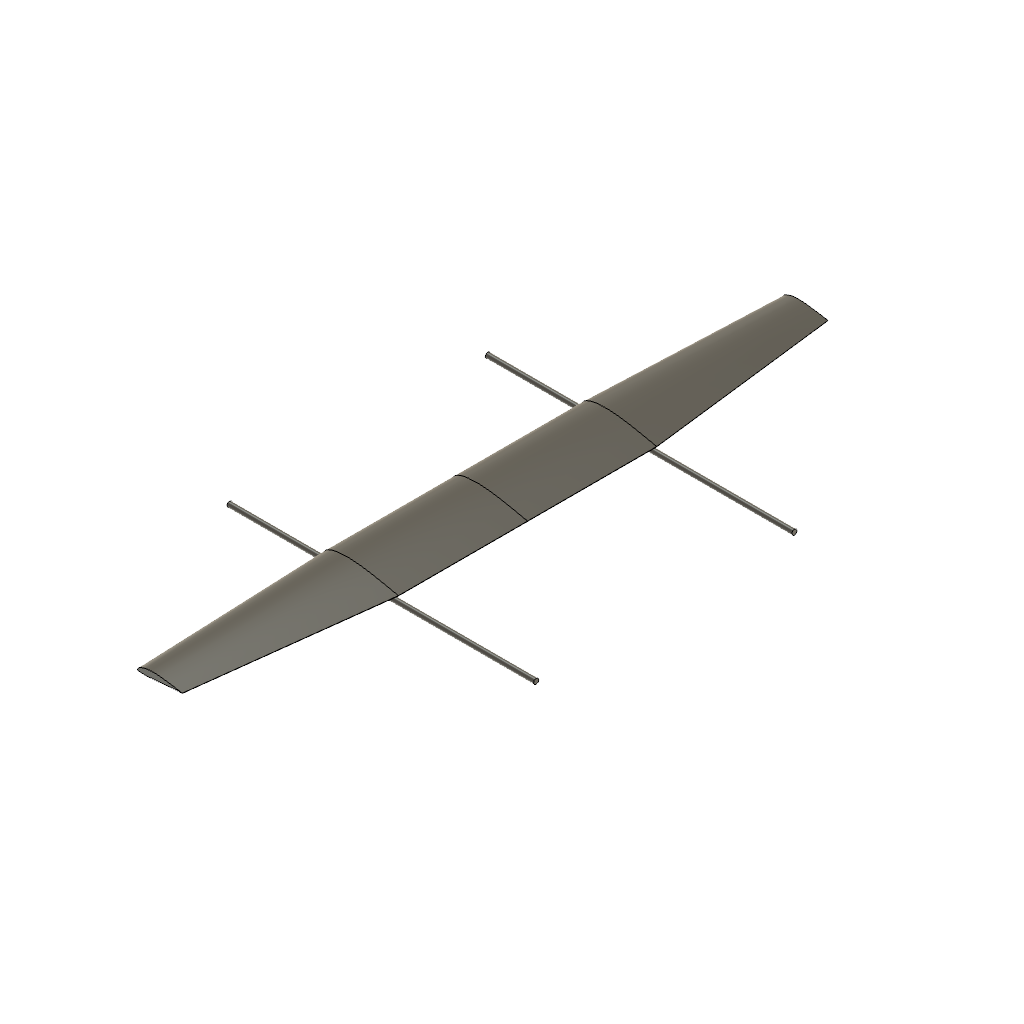
VTOL Wing - Aero OML (Autodesk Fusion 360 design; units mm, degrees)
part number: 2026-10-17-09-22-44-938
part number: 2026-10-17-09-22-45-187
part number: 2026-10-17-09-22-45-715
Autodesk Fusion 360 part; units mm, degrees
(part 1 of 2)
ref_plane "WorkPlane1" through (0, -1000, 0) normal (0, 1, 0) x (0, 0, 1) in component "Wing OML (SD7062, 2 m)"
sketch "Section y=-1000" plane through (0, -1000, 0) normal (0, 1, 0) x (1, 0, 0) in component "Wing OML (SD7062, 2 m)"
  spline S0 degree 5 poles (103.9894, -3.9091) (103.9546, -3.913) (103.8735, -3.9225) (103.7172, -3.942) (103.4393, -3.9785) (102.9897, -4.0405) (102.4668, -4.1159) (101.9003, -4.202) (101.3056, -4.2968) (100.6854, -4.3993) (100.0363, -4.509) (99.3553, -4.6256) (98.6441, -4.7485) (97.906, -4.877) (97.1455, -5.0105) (96.3662, -5.1483) (95.5697, -5.2897) (94.7567, -5.4342) (93.927, -5.5815) (93.0804, -5.7312) (92.2171, -5.883) (91.338, -6.037) (90.444, -6.1931) (89.5363, -6.3512) (88.6159, -6.5114) (87.6835, -6.6736) (86.7397, -6.8378) (85.7847, -7.0039) (84.8189, -7.1719) (83.8425, -7.3417) (82.8558, -7.5131) (81.8592, -7.6861) (80.853, -7.8606) (79.8377, -8.0365) (78.8137, -8.2136) (77.7814, -8.392) (76.7412, -8.5714) (75.6934, -8.7517) (74.6381, -8.9328) (73.5756, -9.1145) (72.506, -9.2967) (71.4297, -9.4792) (70.3468, -9.6618) (69.2576, -9.8446) (68.1623, -10.0272) (67.0611, -10.2097) (65.9544, -10.3918) (64.8422, -10.5733) (63.7249, -10.7541) (62.6025, -10.934) (61.4754, -11.1127) (60.3435, -11.2901) (59.2071, -11.4659) (58.0663, -11.64) (56.9213, -11.8122) (55.7722, -11.9823) (54.6194, -12.1502) (53.4628, -12.3158) (52.3029, -12.479) (51.1396, -12.6396) (49.9733, -12.7975) (48.8041, -12.9525) (47.6321, -13.1045) (46.4575, -13.2533) (45.2804, -13.3986) (44.101, -13.5404) (42.9195, -13.6784) (41.736, -13.8126) (40.5507, -13.9427) (39.3637, -14.0687) (38.1753, -14.1905) (36.9856, -14.3079) (35.7948, -14.4208) (34.603, -14.5291) (33.4104, -14.6328) (32.2172, -14.7315) (31.0236, -14.8251) (29.8296, -14.9136) (28.6355, -14.9967) (27.4415, -15.0742) (26.2477, -15.1461) (25.0543, -15.2122) (23.8616, -15.2723) (22.6696, -15.3263) (21.4787, -15.3742) (20.289, -15.4157) (19.1007, -15.4507) (17.9141, -15.4791) (16.7293, -15.5007) (15.5464, -15.5153) (14.3658, -15.5228) (13.1876, -15.5229) (12.0121, -15.5155) (10.8393, -15.5005) (9.6696, -15.4776) (8.5033, -15.4466) (7.3405, -15.4076) (6.1816, -15.3601) (5.0268, -15.3042) (3.8764, -15.2395) (2.7307, -15.1659) (1.59, -15.0831) (0.4545, -14.9909) (-0.6753, -14.8891) (-1.7992, -14.7774) (-2.9169, -14.6555) (-4.0279, -14.5234) (-5.1321, -14.3808) (-6.229, -14.2276) (-7.3182, -14.0636) (-8.3993, -13.8885) (-9.4719, -13.7021) (-10.5354, -13.5041) (-11.5894, -13.2942) (-12.6332, -13.072) (-13.6663, -12.8371) (-14.688, -12.5894) (-15.698, -12.3284) (-16.6955, -12.0542) (-17.6801, -11.7667) (-18.6511, -11.4659) (-19.6079, -11.1515) (-20.5497, -10.8236) (-21.4754, -10.4816) (-22.3839, -10.125) (-23.2739, -9.753) (-24.1438, -9.3652) (-24.9925, -8.9612) (-25.8188, -8.5411) (-26.622, -8.1055) (-27.4012, -7.6554) (-28.1556, -7.1919) (-28.8836, -6.7153) (-29.5829, -6.2254) (-30.2501, -5.7205) (-30.8811, -5.1987) (-31.4722, -4.6589) (-32.0202, -4.1021) (-32.5241, -3.5326) (-32.9845, -2.9586) (-33.4012, -2.3876) (-33.7716, -1.824) (-34.0876, -1.2648) (-34.3357, -0.6996) (-34.5057, -0.1267) (-34.5969, 0.4365) (-34.6273, 0.9351) (-34.6253, 1.3136) (-34.616, 1.5684) (-34.6144, 1.7803) (-34.5603, 2.036) (-34.36, 2.3782) (-34.0098, 2.7656) (-33.5512, 3.1223) (-33.028, 3.3992) (-32.4588, 3.6037) (-31.8511, 3.7667) (-31.2056, 3.9223) (-30.5251, 4.0821) (-29.8136, 4.2426) (-29.0752, 4.3929) (-28.3137, 4.5228) (-27.5314, 4.6297) (-26.7298, 4.7165) (-25.9098, 4.7888) (-25.072, 4.853) (-24.217, 4.9126) (-23.3459, 4.9686) (-22.4595, 5.0198) (-21.5588, 5.0647) (-20.6447, 5.1014) (-19.7181, 5.1293) (-18.7794, 5.1485) (-17.8292, 5.16) (-16.868, 5.1651) (-15.8961, 5.1647) (-14.9139, 5.1598) (-13.9218, 5.1506) (-12.9203, 5.1371) (-11.9098, 5.1191) (-10.8907, 5.0965) (-9.8633, 5.0689) (-8.828, 5.0366) (-7.7851, 4.9996) (-6.7349, 4.9582) (-5.6776, 4.9128) (-4.6137, 4.8637) (-3.5432, 4.8112) (-2.4665, 4.7554) (-1.3838, 4.6965) (-0.2955, 4.6343) (0.7984, 4.5691) (1.8974, 4.5008) (3.0014, 4.4294) (4.1101, 4.355) (5.2234, 4.2777) (6.341, 4.1977) (7.4628, 4.1151) (8.5884, 4.0299) (9.7178, 3.9423) (10.8507, 3.8523) (11.987, 3.76) (13.1265, 3.6655) (14.269, 3.5688) (15.4143, 3.47) (16.5622, 3.3691) (17.7126, 3.2661) (18.8653, 3.1613) (20.02, 3.0547) (21.1766, 2.9464) (22.335, 2.8365) (23.4948, 2.7252) (24.6561, 2.6126) (25.8186, 2.4988) (26.9821, 2.3839) (28.1467, 2.268) (29.312, 2.1512) (30.478, 2.0337) (31.6445, 1.9154) (32.8114, 1.7964) (33.9784, 1.677) (35.1455, 1.5571) (36.3124, 1.4369) (37.479, 1.3164) (38.6451, 1.1957) (39.8105, 1.0749) (40.9751, 0.9542) (42.1387, 0.8336) (43.3011, 0.7133) (44.4623, 0.5932) (45.6221, 0.4736) (46.7803, 0.3545) (47.9367, 0.236) (49.0912, 0.1182) (50.2436, 0.0011) (51.3938, -0.1151) (52.5415, -0.2305) (53.6867, -0.3449) (54.8291, -0.4582) (55.9685, -0.5704) (57.1048, -0.6815) (58.2378, -0.7912) (59.3672, -0.8996) (60.4929, -1.0066) (61.6147, -1.1122) (62.7324, -1.2161) (63.8458, -1.3185) (64.9547, -1.4192) (66.0589, -1.5182) (67.1581, -1.6153) (68.2522, -1.7106) (69.3409, -1.8039) (70.4239, -1.8952) (71.5011, -1.9843) (72.5722, -2.0713) (73.6369, -2.156) (74.6949, -2.2385) (75.7461, -2.3187) (76.7902, -2.3965) (77.8269, -2.472) (78.8559, -2.5452) (79.8769, -2.616) (80.8895, -2.6844) (81.8933, -2.7502) (82.8878, -2.8135) (83.8727, -2.874) (84.8475, -2.9317) (85.8119, -2.9865) (86.7656, -3.0383) (87.7083, -3.0873) (88.6398, -3.1332) (89.5596, -3.1762) (90.4669, -3.2162) (91.3608, -3.2531) (92.2403, -3.2868) (93.1042, -3.3172) (93.9516, -3.3443) (94.782, -3.3679) (95.5956, -3.3879) (96.3925, -3.4044) (97.1722, -3.4173) (97.9332, -3.4267) (98.6724, -3.4331) (99.3851, -3.4365) (100.0673, -3.4373) (100.7169, -3.4355) (101.3362, -3.4305) (101.9288, -3.4217) (102.4929, -3.4091) (103.0142, -3.3935) (103.4629, -3.3776) (103.7397, -3.3666) (103.8946, -3.3599) (103.9746, -3.3561) (104.0088, -3.3544) knots 0 0 0 0 0 0 0.00344828 0.00689655 0.01034483 0.0137931 0.01724138 0.02068966 0.02413793 0.02758621 0.03103448 0.03448276 0.03793103 0.04137931 0.04482759 0.04827586 0.05172414 0.05517241 0.05862069 0.06206897 0.06551724 0.06896552 0.07241379 0.07586207 0.07931034 0.08275862 0.0862069 0.08965517 0.09310345 0.09655172 0.1 0.10344828 0.10689655 0.11034483 0.1137931 0.11724138 0.12068966 0.12413793 0.12758621 0.13103448 0.13448276 0.13793103 0.14137931 0.14482759 0.14827586 0.15172414 0.15517241 0.15862069 0.16206897 0.16551724 0.16896552 0.17241379 0.17586207 0.17931034 0.18275862 0.1862069 0.18965517 0.19310345 0.19655172 0.2 0.20344828 0.20689655 0.21034483 0.2137931 0.21724138 0.22068966 0.22413793 0.22758621 0.23103448 0.23448276 0.23793103 0.24137931 0.24482759 0.24827586 0.25172414 0.25517241 0.25862069 0.26206897 0.26551724 0.26896552 0.27241379 0.27586207 0.27931034 0.28275862 0.2862069 0.28965517 0.29310345 0.29655172 0.3 0.30344828 0.30689655 0.31034483 0.3137931 0.31724138 0.32068966 0.32413793 0.32758621 0.33103448 0.33448276 0.33793103 0.34137931 0.34482759 0.34827586 0.35172414 0.35517241 0.35862069 0.36206897 0.36551724 0.36896552 0.37241379 0.37586207 0.37931034 0.38275862 0.3862069 0.38965517 0.39310345 0.39655172 0.4 0.40344828 0.40689655 0.41034483 0.4137931 0.41724138 0.42068966 0.42413793 0.42758621 0.43103448 0.43448276 0.43793103 0.44137931 0.44482759 0.44827586 0.45172414 0.45517241 0.45862069 0.46206897 0.46551724 0.46896552 0.47241379 0.47586207 0.47931034 0.48275862 0.4862069 0.48965517 0.49310345 0.49655172 0.5 0.50344828 0.50689655 0.51034483 0.5137931 0.51724138 0.52068966 0.52413793 0.52758621 0.53103448 0.53448276 0.53793103 0.54137931 0.54482759 0.54827586 0.55172414 0.55517241 0.55862069 0.56206897 0.56551724 0.56896552 0.57241379 0.57586207 0.57931034 0.58275862 0.5862069 0.58965517 0.59310345 0.59655172 0.6 0.60344828 0.60689655 0.61034483 0.6137931 0.61724138 0.62068966 0.62413793 0.62758621 0.63103448 0.63448276 0.63793103 0.64137931 0.64482759 0.64827586 0.65172414 0.65517241 0.65862069 0.66206897 0.66551724 0.66896552 0.67241379 0.67586207 0.67931034 0.68275862 0.6862069 0.68965517 0.69310345 0.69655172 0.7 0.70344828 0.70689655 0.71034483 0.7137931 0.71724138 0.72068966 0.72413793 0.72758621 0.73103448 0.73448276 0.73793103 0.74137931 0.74482759 0.74827586 0.75172414 0.75517241 0.75862069 0.76206897 0.76551724 0.76896552 0.77241379 0.77586207 0.77931034 0.78275862 0.7862069 0.78965517 0.79310345 0.79655172 0.8 0.80344828 0.80689655 0.81034483 0.8137931 0.81724138 0.82068966 0.82413793 0.82758621 0.83103448 0.83448276 0.83793103 0.84137931 0.84482759 0.84827586 0.85172414 0.85517241 0.85862069 0.86206897 0.86551724 0.86896552 0.87241379 0.87586207 0.87931034 0.88275862 0.8862069 0.88965517 0.89310345 0.89655172 0.9 0.90344828 0.90689655 0.91034483 0.9137931 0.91724138 0.92068966 0.92413793 0.92758621 0.93103448 0.93448276 0.93793103 0.94137931 0.94482759 0.94827586 0.95172414 0.95517241 0.95862069 0.96206897 0.96551724 0.96896552 0.97241379 0.97586207 0.97931034 0.98275862 0.9862069 0.98965517 0.99310345 0.99655172 1 1 1 1 1 1
  line L0 (104.0088, -3.3544) -> (103.9894, -3.9091)
  point P0 (103.5655, -3.9623)
  point P1 (102.3014, -4.1417)
  point P2 (100.2182, -4.4785)
  point P3 (97.3408, -4.9764)
  point P4 (93.7017, -5.6212)
  point P5 (89.3406, -6.3852)
  point P6 (84.3092, -7.2605)
  point P7 (78.6647, -8.2393)
  point P8 (72.4745, -9.3018)
  point P9 (65.8062, -10.4157)
  point P10 (58.7351, -11.5376)
  point P11 (51.3352, -12.612)
  point P12 (43.6916, -13.5877)
  point P13 (35.8909, -14.4107)
  point P14 (28.0249, -15.0357)
  point P15 (20.1882, -15.4173)
  point P16 (12.4822, -15.5175)
  point P17 (5.0052, -15.3008)
  point P18 (-2.1363, -14.739)
  point P19 (-8.836, -13.8109)
  point P20 (-14.984, -12.5105)
  point P21 (-20.4695, -10.8473)
  point P22 (-25.1803, -8.8613)
  point P23 (-29.0048, -6.6244)
  point P24 (-31.8531, -4.2633)
  point P25 (-33.6642, -1.976)
  point P26 (-34.5072, -0.0348)
  point P27 (-34.6239, 1.2341)
  point P28 (-34.6131, 1.6627)
  point P29 (-34.5228, 2.0608)
  point P30 (-33.6919, 2.9953)
  point P31 (-31.8211, 3.7699)
  point P32 (-29.084, 4.3852)
  point P33 (-25.5593, 4.8146)
  point P34 (-21.3144, 5.0732)
  point P35 (-16.409, 5.1643)
  point P36 (-10.908, 5.0957)
  point P37 (-4.8792, 4.8755)
  point P38 (1.6044, 4.5186)
  point P39 (8.4642, 4.0388)
  point P40 (15.62, 3.4516)
  point P41 (22.9893, 2.7736)
  point P42 (30.4841, 2.0329)
  point P43 (38.0222, 1.2601)
  point P44 (45.5144, 0.4848)
  point P45 (52.8757, -0.2637)
  point P46 (60.0221, -0.9617)
  point P47 (66.8697, -1.5896)
  point P48 (73.3385, -2.132)
  point P49 (79.3538, -2.5795)
  point P50 (84.8436, -2.9309)
  point P51 (89.7426, -3.1839)
  point P52 (93.9922, -3.3448)
  point P53 (97.5409, -3.4215)
  point P54 (100.3463, -3.4361)
  point P55 (102.3727, -3.4111)
  point P56 (103.5986, -3.372)
ref_plane "WorkPlane2" through (0, -400, 0) normal (0, 1, 0) x (0, 0, 1) in component "Wing OML (SD7062, 2 m)"
sketch "Section y=-400" plane through (0, -400, 0) normal (0, 1, 0) x (1, 0, 0) in component "Wing OML (SD7062, 2 m)"
  spline S0 degree 5 poles (173.4375, -0.4625) (173.3779, -0.4713) (173.2398, -0.4925) (172.9754, -0.5349) (172.508, -0.6131) (171.7554, -0.7438) (170.8834, -0.9011) (169.9408, -1.0785) (168.9525, -1.2718) (167.9224, -1.4794) (166.8445, -1.7007) (165.7141, -1.9352) (164.5339, -2.1819) (163.3097, -2.4395) (162.0489, -2.7065) (160.7573, -2.9816) (159.4376, -3.2638) (158.0906, -3.5521) (156.7161, -3.8459) (155.3137, -4.1446) (153.8838, -4.4479) (152.4278, -4.7557) (150.9472, -5.0677) (149.4441, -5.3839) (147.9201, -5.7042) (146.3763, -6.0287) (144.8138, -6.3571) (143.2329, -6.6894) (141.6342, -7.0253) (140.018, -7.3648) (138.3848, -7.7076) (136.7352, -8.0536) (135.0699, -8.4027) (133.3896, -8.7546) (131.695, -9.1091) (129.9867, -9.4661) (128.2654, -9.8252) (126.5313, -10.1863) (124.7851, -10.5491) (123.0268, -10.9133) (121.257, -11.2787) (119.476, -11.645) (117.684, -12.012) (115.8816, -12.3794) (114.069, -12.747) (112.2468, -13.1147) (110.4153, -13.482) (108.5748, -13.8487) (106.7256, -14.2145) (104.8681, -14.5791) (103.0025, -14.942) (101.1291, -15.3029) (99.248, -15.6615) (97.3595, -16.0174) (95.464, -16.3704) (93.5617, -16.7202) (91.6529, -17.0666) (89.7379, -17.4093) (87.817, -17.7482) (85.8906, -18.083) (83.9589, -18.4134) (82.0221, -18.7393) (80.0807, -19.0603) (78.1347, -19.376) (76.1844, -19.6862) (74.2301, -19.9906) (72.2721, -20.2889) (70.3105, -20.5809) (68.3457, -20.8663) (66.3779, -21.1449) (64.4074, -21.4165) (62.4345, -21.681) (60.4595, -21.9381) (58.4827, -22.1876) (56.5043, -22.4294) (54.5246, -22.663) (52.5438, -22.8882) (50.5622, -23.1048) (48.5801, -23.3125) (46.5977, -23.511) (44.6154, -23.7) (42.6334, -23.8794) (40.6522, -24.0488) (38.6719, -24.2081) (36.693, -24.357) (34.7157, -24.4954) (32.7404, -24.6228) (30.7674, -24.7392) (28.797, -24.8442) (26.8296, -24.9374) (24.8654, -25.0186) (22.9047, -25.0875) (20.948, -25.1438) (18.9955, -25.1871) (17.0477, -25.2173) (15.1049, -25.2339) (13.1675, -25.2367) (11.2361, -25.2255) (9.3109, -25.1999) (7.3926, -25.1595) (5.4815, -25.104) (3.5781, -25.0329) (1.683, -24.9459) (-0.2034, -24.8426) (-2.0806, -24.7225) (-3.948, -24.5852) (-5.8051, -24.4305) (-7.6513, -24.2579) (-9.4861, -24.0673) (-11.3088, -23.8582) (-13.1187, -23.6303) (-14.9152, -23.3831) (-16.6973, -23.1162) (-18.4643, -22.8288) (-20.2152, -22.5205) (-21.949, -22.1905) (-23.6649, -21.8383) (-25.3618, -21.4636) (-27.039, -21.0661) (-28.6954, -20.6457) (-30.3303, -20.2023) (-31.9423, -19.7357) (-33.5302, -19.2456) (-35.0925, -18.7312) (-36.627, -18.1914) (-38.1316, -17.6252) (-39.604, -17.0314) (-41.0421, -16.4093) (-42.4441, -15.7591) (-43.8086, -15.0816) (-45.1342, -14.3787) (-46.4193, -13.6517) (-47.6616, -12.9015) (-48.8572, -12.1275) (-50.0006, -11.3267) (-51.0851, -10.4957) (-52.1043, -9.6324) (-53.0531, -8.7378) (-53.9292, -7.819) (-54.7331, -6.8893) (-55.4645, -5.9614) (-56.1187, -5.043) (-56.6829, -4.1292) (-57.135, -3.2016) (-57.4573, -2.2557) (-57.647, -1.3186) (-57.7297, -0.4816) (-57.7502, 0.1595) (-57.7499, 0.5935) (-57.7591, 0.9541) (-57.6812, 1.3907) (-57.3606, 1.9785) (-56.7919, 2.6466) (-56.042, 3.2659) (-55.1817, 3.7543) (-54.2419, 4.1256) (-53.2361, 4.4315) (-52.167, 4.7287) (-51.04, 5.0349) (-49.8616, 5.3437) (-48.6381, 5.6364) (-47.3752, 5.8957) (-46.0767, 6.118) (-44.7453, 6.3081) (-43.3825, 6.4756) (-41.9898, 6.6308) (-40.5684, 6.7797) (-39.1198, 6.9232) (-37.6457, 7.0599) (-36.1476, 7.1866) (-34.6269, 7.3004) (-33.0848, 7.4001) (-31.5223, 7.4862) (-29.9403, 7.5603) (-28.3396, 7.6242) (-26.721, 7.6798) (-25.085, 7.7285) (-23.4324, 7.7706) (-21.764, 7.8062) (-20.0803, 7.8348) (-18.3821, 7.8561) (-16.6699, 7.8697) (-14.9443, 7.8758) (-13.2058, 7.8746) (-11.455, 7.8666) (-9.6924, 7.8523) (-7.9183, 7.8323) (-6.1333, 7.807) (-4.3378, 7.7766) (-2.5322, 7.7412) (-0.7169, 7.701) (1.1075, 7.6558) (2.9408, 7.6059) (4.7825, 7.5511) (6.6322, 7.4917) (8.4896, 7.4277) (10.3544, 7.3594) (12.2261, 7.2869) (14.1044, 7.2105) (15.9891, 7.1303) (17.8799, 7.0463) (19.7763, 6.9588) (21.6781, 6.8677) (23.5851, 6.7731) (25.4968, 6.6752) (27.4131, 6.5739) (29.3335, 6.4694) (31.2577, 6.3619) (33.1855, 6.2515) (35.1166, 6.1385) (37.0505, 6.023) (38.9871, 5.9052) (40.9261, 5.7853) (42.8672, 5.6634) (44.8102, 5.5398) (46.7548, 5.4146) (48.7007, 5.288) (50.6479, 5.1601) (52.5959, 5.031) (54.5445, 4.901) (56.4935, 4.77) (58.4425, 4.6383) (60.3913, 4.506) (62.3396, 4.3733) (64.2871, 4.2403) (66.2334, 4.1071) (68.1784, 3.9738) (70.1218, 3.8408) (72.0632, 3.708) (74.0025, 3.5758) (75.9394, 3.4441) (77.8737, 3.3132) (79.805, 3.1832) (81.7331, 3.0542) (83.6577, 2.9264) (85.5785, 2.7997) (87.4953, 2.6744) (89.4077, 2.5506) (91.3155, 2.4284) (93.2183, 2.3078) (95.1159, 2.189) (97.0078, 2.0721) (98.8938, 1.9573) (100.7736, 1.8446) (102.6468, 1.7341) (104.5131, 1.626) (106.3722, 1.5203) (108.2237, 1.4171) (110.0673, 1.3165) (111.9026, 1.2186) (113.7293, 1.1235) (115.5469, 1.0314) (117.3551, 0.9423) (119.1534, 0.8564) (120.9414, 0.7738) (122.7188, 0.6946) (124.485, 0.6187) (126.2397, 0.5463) (127.9825, 0.4773) (129.713, 0.4117) (131.4306, 0.3496) (133.1347, 0.2909) (134.8248, 0.2358) (136.5002, 0.1844) (138.1601, 0.1368) (139.8038, 0.0932) (141.4307, 0.0536) (143.0402, 0.0183) (144.6317, -0.0128) (146.205, -0.0397) (147.7594, -0.0622) (149.2942, -0.0805) (150.8084, -0.0944) (152.3002, -0.1041) (153.7678, -0.1093) (155.2095, -0.1099) (156.6237, -0.1059) (158.0095, -0.0971) (159.3671, -0.0834) (160.6968, -0.0647) (161.9979, -0.041) (163.2682, -0.0127) (164.5022, 0.0197) (165.6923, 0.0553) (166.8319, 0.0935) (167.9171, 0.1343) (168.9516, 0.1785) (169.9416, 0.2275) (170.8846, 0.2813) (171.7577, 0.3377) (172.5117, 0.3908) (172.9791, 0.4257) (173.2421, 0.4462) (173.3788, 0.4575) (173.4375, 0.4625) knots 0 0 0 0 0 0 0.00344828 0.00689655 0.01034483 0.0137931 0.01724138 0.02068966 0.02413793 0.02758621 0.03103448 0.03448276 0.03793103 0.04137931 0.04482759 0.04827586 0.05172414 0.05517241 0.05862069 0.06206897 0.06551724 0.06896552 0.07241379 0.07586207 0.07931034 0.08275862 0.0862069 0.08965517 0.09310345 0.09655172 0.1 0.10344828 0.10689655 0.11034483 0.1137931 0.11724138 0.12068966 0.12413793 0.12758621 0.13103448 0.13448276 0.13793103 0.14137931 0.14482759 0.14827586 0.15172414 0.15517241 0.15862069 0.16206897 0.16551724 0.16896552 0.17241379 0.17586207 0.17931034 0.18275862 0.1862069 0.18965517 0.19310345 0.19655172 0.2 0.20344828 0.20689655 0.21034483 0.2137931 0.21724138 0.22068966 0.22413793 0.22758621 0.23103448 0.23448276 0.23793103 0.24137931 0.24482759 0.24827586 0.25172414 0.25517241 0.25862069 0.26206897 0.26551724 0.26896552 0.27241379 0.27586207 0.27931034 0.28275862 0.2862069 0.28965517 0.29310345 0.29655172 0.3 0.30344828 0.30689655 0.31034483 0.3137931 0.31724138 0.32068966 0.32413793 0.32758621 0.33103448 0.33448276 0.33793103 0.34137931 0.34482759 0.34827586 0.35172414 0.35517241 0.35862069 0.36206897 0.36551724 0.36896552 0.37241379 0.37586207 0.37931034 0.38275862 0.3862069 0.38965517 0.39310345 0.39655172 0.4 0.40344828 0.40689655 0.41034483 0.4137931 0.41724138 0.42068966 0.42413793 0.42758621 0.43103448 0.43448276 0.43793103 0.44137931 0.44482759 0.44827586 0.45172414 0.45517241 0.45862069 0.46206897 0.46551724 0.46896552 0.47241379 0.47586207 0.47931034 0.48275862 0.4862069 0.48965517 0.49310345 0.49655172 0.5 0.50344828 0.50689655 0.51034483 0.5137931 0.51724138 0.52068966 0.52413793 0.52758621 0.53103448 0.53448276 0.53793103 0.54137931 0.54482759 0.54827586 0.55172414 0.55517241 0.55862069 0.56206897 0.56551724 0.56896552 0.57241379 0.57586207 0.57931034 0.58275862 0.5862069 0.58965517 0.59310345 0.59655172 0.6 0.60344828 0.60689655 0.61034483 0.6137931 0.61724138 0.62068966 0.62413793 0.62758621 0.63103448 0.63448276 0.63793103 0.64137931 0.64482759 0.64827586 0.65172414 0.65517241 0.65862069 0.66206897 0.66551724 0.66896552 0.67241379 0.67586207 0.67931034 0.68275862 0.6862069 0.68965517 0.69310345 0.69655172 0.7 0.70344828 0.70689655 0.71034483 0.7137931 0.71724138 0.72068966 0.72413793 0.72758621 0.73103448 0.73448276 0.73793103 0.74137931 0.74482759 0.74827586 0.75172414 0.75517241 0.75862069 0.76206897 0.76551724 0.76896552 0.77241379 0.77586207 0.77931034 0.78275862 0.7862069 0.78965517 0.79310345 0.79655172 0.8 0.80344828 0.80689655 0.81034483 0.8137931 0.81724138 0.82068966 0.82413793 0.82758621 0.83103448 0.83448276 0.83793103 0.84137931 0.84482759 0.84827586 0.85172414 0.85517241 0.85862069 0.86206897 0.86551724 0.86896552 0.87241379 0.87586207 0.87931034 0.88275862 0.8862069 0.88965517 0.89310345 0.89655172 0.9 0.90344828 0.90689655 0.91034483 0.9137931 0.91724138 0.92068966 0.92413793 0.92758621 0.93103448 0.93448276 0.93793103 0.94137931 0.94482759 0.94827586 0.95172414 0.95517241 0.95862069 0.96206897 0.96551724 0.96896552 0.97241379 0.97586207 0.97931034 0.98275862 0.9862069 0.98965517 0.99310345 0.99655172 1 1 1 1 1 1
  line L0 (173.4375, 0.4625) -> (173.4375, -0.4625)
  point P0 (172.7345, -0.5758)
  point P1 (170.6394, -0.9481)
  point P2 (167.1891, -1.6303)
  point P3 (162.4254, -2.627)
  point P4 (156.4013, -3.9128)
  point P5 (149.1817, -5.439)
  point P6 (140.8521, -7.1896)
  point P7 (131.5072, -9.1482)
  point P8 (121.2583, -11.2781)
  point P9 (110.2161, -13.5212)
  point P10 (98.5032, -15.8013)
  point P11 (86.2401, -18.0213)
  point P12 (73.5652, -20.091)
  point P13 (60.6199, -21.9156)
  point P14 (47.5542, -23.4141)
  point P15 (34.5233, -24.5056)
  point P16 (21.6936, -25.1207)
  point P17 (9.2269, -25.1947)
  point P18 (-2.701, -24.6744)
  point P19 (-13.9143, -23.5181)
  point P20 (-24.2304, -21.7097)
  point P21 (-33.4642, -19.2585)
  point P22 (-41.4261, -16.2245)
  point P23 (-47.9266, -12.7211)
  point P24 (-52.8083, -8.954)
  point P25 (-55.9579, -5.2494)
  point P26 (-57.4749, -2.0651)
  point P27 (-57.7431, 0.0416)
  point P28 (-57.7501, 0.7562)
  point P29 (-57.6229, 1.4245)
  point P30 (-56.2932, 3.0294)
  point P31 (-53.2222, 4.4284)
  point P32 (-48.6989, 5.6124)
  point P33 (-42.8529, 6.5328)
  point P34 (-35.7975, 7.2104)
  point P35 (-27.6321, 7.6474)
  point P36 (-18.4653, 7.8532)
  point P37 (-8.4106, 7.8371)
  point P38 (2.4096, 7.6197)
  point P39 (13.8634, 7.2196)
  point P40 (25.8168, 6.6577)
  point P41 (38.1308, 5.957)
  point P42 (50.6576, 5.1592)
  point P43 (63.2584, 4.3105)
  point P44 (75.7829, 3.4549)
  point P45 (88.0877, 2.6362)
  point P46 (100.0318, 1.8893)
  point P47 (111.4741, 1.2418)
  point P48 (122.2804, 0.7146)
  point P49 (132.3259, 0.3191)
  point P50 (141.4903, 0.0532)
  point P51 (149.665, -0.0833)
  point P52 (156.7528, -0.1041)
  point P53 (162.6682, -0.0254)
  point P54 (167.3417, 0.1133)
  point P55 (170.7157, 0.2729)
  point P56 (172.7553, 0.4093)
sketch "Section y=0" plane through (0, 0, 0) normal (0, 1, 0) x (1, 0, 0) in component "Wing OML (SD7062, 2 m)"
  spline S0 degree 5 poles (173.4375, -0.4625) (173.3779, -0.4713) (173.2398, -0.4925) (172.9754, -0.5349) (172.508, -0.6131) (171.7554, -0.7438) (170.8834, -0.9011) (169.9408, -1.0785) (168.9525, -1.2718) (167.9224, -1.4794) (166.8445, -1.7007) (165.7141, -1.9352) (164.5339, -2.1819) (163.3097, -2.4395) (162.0489, -2.7065) (160.7573, -2.9816) (159.4376, -3.2638) (158.0906, -3.5521) (156.7161, -3.8459) (155.3137, -4.1446) (153.8838, -4.4479) (152.4278, -4.7557) (150.9472, -5.0677) (149.4441, -5.3839) (147.9201, -5.7042) (146.3763, -6.0287) (144.8138, -6.3571) (143.2329, -6.6894) (141.6342, -7.0253) (140.018, -7.3648) (138.3848, -7.7076) (136.7352, -8.0536) (135.0699, -8.4027) (133.3896, -8.7546) (131.695, -9.1091) (129.9867, -9.4661) (128.2654, -9.8252) (126.5313, -10.1863) (124.7851, -10.5491) (123.0268, -10.9133) (121.257, -11.2787) (119.476, -11.645) (117.684, -12.012) (115.8816, -12.3794) (114.069, -12.747) (112.2468, -13.1147) (110.4153, -13.482) (108.5748, -13.8487) (106.7256, -14.2145) (104.8681, -14.5791) (103.0025, -14.942) (101.1291, -15.3029) (99.248, -15.6615) (97.3595, -16.0174) (95.464, -16.3704) (93.5617, -16.7202) (91.6529, -17.0666) (89.7379, -17.4093) (87.817, -17.7482) (85.8906, -18.083) (83.9589, -18.4134) (82.0221, -18.7393) (80.0807, -19.0603) (78.1347, -19.376) (76.1844, -19.6862) (74.2301, -19.9906) (72.2721, -20.2889) (70.3105, -20.5809) (68.3457, -20.8663) (66.3779, -21.1449) (64.4074, -21.4165) (62.4345, -21.681) (60.4595, -21.9381) (58.4827, -22.1876) (56.5043, -22.4294) (54.5246, -22.663) (52.5438, -22.8882) (50.5622, -23.1048) (48.5801, -23.3125) (46.5977, -23.511) (44.6154, -23.7) (42.6334, -23.8794) (40.6522, -24.0488) (38.6719, -24.2081) (36.693, -24.357) (34.7157, -24.4954) (32.7404, -24.6228) (30.7674, -24.7392) (28.797, -24.8442) (26.8296, -24.9374) (24.8654, -25.0186) (22.9047, -25.0875) (20.948, -25.1438) (18.9955, -25.1871) (17.0477, -25.2173) (15.1049, -25.2339) (13.1675, -25.2367) (11.2361, -25.2255) (9.3109, -25.1999) (7.3926, -25.1595) (5.4815, -25.104) (3.5781, -25.0329) (1.683, -24.9459) (-0.2034, -24.8426) (-2.0806, -24.7225) (-3.948, -24.5852) (-5.8051, -24.4305) (-7.6513, -24.2579) (-9.4861, -24.0673) (-11.3088, -23.8582) (-13.1187, -23.6303) (-14.9152, -23.3831) (-16.6973, -23.1162) (-18.4643, -22.8288) (-20.2152, -22.5205) (-21.949, -22.1905) (-23.6649, -21.8383) (-25.3618, -21.4636) (-27.039, -21.0661) (-28.6954, -20.6457) (-30.3303, -20.2023) (-31.9423, -19.7357) (-33.5302, -19.2456) (-35.0925, -18.7312) (-36.627, -18.1914) (-38.1316, -17.6252) (-39.604, -17.0314) (-41.0421, -16.4093) (-42.4441, -15.7591) (-43.8086, -15.0816) (-45.1342, -14.3787) (-46.4193, -13.6517) (-47.6616, -12.9015) (-48.8572, -12.1275) (-50.0006, -11.3267) (-51.0851, -10.4957) (-52.1043, -9.6324) (-53.0531, -8.7378) (-53.9292, -7.819) (-54.7331, -6.8893) (-55.4645, -5.9614) (-56.1187, -5.043) (-56.6829, -4.1292) (-57.135, -3.2016) (-57.4573, -2.2557) (-57.647, -1.3186) (-57.7297, -0.4816) (-57.7502, 0.1595) (-57.7499, 0.5935) (-57.7591, 0.9541) (-57.6812, 1.3907) (-57.3606, 1.9785) (-56.7919, 2.6466) (-56.042, 3.2659) (-55.1817, 3.7543) (-54.2419, 4.1256) (-53.2361, 4.4315) (-52.167, 4.7287) (-51.04, 5.0349) (-49.8616, 5.3437) (-48.6381, 5.6364) (-47.3752, 5.8957) (-46.0767, 6.118) (-44.7453, 6.3081) (-43.3825, 6.4756) (-41.9898, 6.6308) (-40.5684, 6.7797) (-39.1198, 6.9232) (-37.6457, 7.0599) (-36.1476, 7.1866) (-34.6269, 7.3004) (-33.0848, 7.4001) (-31.5223, 7.4862) (-29.9403, 7.5603) (-28.3396, 7.6242) (-26.721, 7.6798) (-25.085, 7.7285) (-23.4324, 7.7706) (-21.764, 7.8062) (-20.0803, 7.8348) (-18.3821, 7.8561) (-16.6699, 7.8697) (-14.9443, 7.8758) (-13.2058, 7.8746) (-11.455, 7.8666) (-9.6924, 7.8523) (-7.9183, 7.8323) (-6.1333, 7.807) (-4.3378, 7.7766) (-2.5322, 7.7412) (-0.7169, 7.701) (1.1075, 7.6558) (2.9408, 7.6059) (4.7825, 7.5511) (6.6322, 7.4917) (8.4896, 7.4277) (10.3544, 7.3594) (12.2261, 7.2869) (14.1044, 7.2105) (15.9891, 7.1303) (17.8799, 7.0463) (19.7763, 6.9588) (21.6781, 6.8677) (23.5851, 6.7731) (25.4968, 6.6752) (27.4131, 6.5739) (29.3335, 6.4694) (31.2577, 6.3619) (33.1855, 6.2515) (35.1166, 6.1385) (37.0505, 6.023) (38.9871, 5.9052) (40.9261, 5.7853) (42.8672, 5.6634) (44.8102, 5.5398) (46.7548, 5.4146) (48.7007, 5.288) (50.6479, 5.1601) (52.5959, 5.031) (54.5445, 4.901) (56.4935, 4.77) (58.4425, 4.6383) (60.3913, 4.506) (62.3396, 4.3733) (64.2871, 4.2403) (66.2334, 4.1071) (68.1784, 3.9738) (70.1218, 3.8408) (72.0632, 3.708) (74.0025, 3.5758) (75.9394, 3.4441) (77.8737, 3.3132) (79.805, 3.1832) (81.7331, 3.0542) (83.6577, 2.9264) (85.5785, 2.7997) (87.4953, 2.6744) (89.4077, 2.5506) (91.3155, 2.4284) (93.2183, 2.3078) (95.1159, 2.189) (97.0078, 2.0721) (98.8938, 1.9573) (100.7736, 1.8446) (102.6468, 1.7341) (104.5131, 1.626) (106.3722, 1.5203) (108.2237, 1.4171) (110.0673, 1.3165) (111.9026, 1.2186) (113.7293, 1.1235) (115.5469, 1.0314) (117.3551, 0.9423) (119.1534, 0.8564) (120.9414, 0.7738) (122.7188, 0.6946) (124.485, 0.6187) (126.2397, 0.5463) (127.9825, 0.4773) (129.713, 0.4117) (131.4306, 0.3496) (133.1347, 0.2909) (134.8248, 0.2358) (136.5002, 0.1844) (138.1601, 0.1368) (139.8038, 0.0932) (141.4307, 0.0536) (143.0402, 0.0183) (144.6317, -0.0128) (146.205, -0.0397) (147.7594, -0.0622) (149.2942, -0.0805) (150.8084, -0.0944) (152.3002, -0.1041) (153.7678, -0.1093) (155.2095, -0.1099) (156.6237, -0.1059) (158.0095, -0.0971) (159.3671, -0.0834) (160.6968, -0.0647) (161.9979, -0.041) (163.2682, -0.0127) (164.5022, 0.0197) (165.6923, 0.0553) (166.8319, 0.0935) (167.9171, 0.1343) (168.9516, 0.1785) (169.9416, 0.2275) (170.8846, 0.2813) (171.7577, 0.3377) (172.5117, 0.3908) (172.9791, 0.4257) (173.2421, 0.4462) (173.3788, 0.4575) (173.4375, 0.4625) knots 0 0 0 0 0 0 0.00344828 0.00689655 0.01034483 0.0137931 0.01724138 0.02068966 0.02413793 0.02758621 0.03103448 0.03448276 0.03793103 0.04137931 0.04482759 0.04827586 0.05172414 0.05517241 0.05862069 0.06206897 0.06551724 0.06896552 0.07241379 0.07586207 0.07931034 0.08275862 0.0862069 0.08965517 0.09310345 0.09655172 0.1 0.10344828 0.10689655 0.11034483 0.1137931 0.11724138 0.12068966 0.12413793 0.12758621 0.13103448 0.13448276 0.13793103 0.14137931 0.14482759 0.14827586 0.15172414 0.15517241 0.15862069 0.16206897 0.16551724 0.16896552 0.17241379 0.17586207 0.17931034 0.18275862 0.1862069 0.18965517 0.19310345 0.19655172 0.2 0.20344828 0.20689655 0.21034483 0.2137931 0.21724138 0.22068966 0.22413793 0.22758621 0.23103448 0.23448276 0.23793103 0.24137931 0.24482759 0.24827586 0.25172414 0.25517241 0.25862069 0.26206897 0.26551724 0.26896552 0.27241379 0.27586207 0.27931034 0.28275862 0.2862069 0.28965517 0.29310345 0.29655172 0.3 0.30344828 0.30689655 0.31034483 0.3137931 0.31724138 0.32068966 0.32413793 0.32758621 0.33103448 0.33448276 0.33793103 0.34137931 0.34482759 0.34827586 0.35172414 0.35517241 0.35862069 0.36206897 0.36551724 0.36896552 0.37241379 0.37586207 0.37931034 0.38275862 0.3862069 0.38965517 0.39310345 0.39655172 0.4 0.40344828 0.40689655 0.41034483 0.4137931 0.41724138 0.42068966 0.42413793 0.42758621 0.43103448 0.43448276 0.43793103 0.44137931 0.44482759 0.44827586 0.45172414 0.45517241 0.45862069 0.46206897 0.46551724 0.46896552 0.47241379 0.47586207 0.47931034 0.48275862 0.4862069 0.48965517 0.49310345 0.49655172 0.5 0.50344828 0.50689655 0.51034483 0.5137931 0.51724138 0.52068966 0.52413793 0.52758621 0.53103448 0.53448276 0.53793103 0.54137931 0.54482759 0.54827586 0.55172414 0.55517241 0.55862069 0.56206897 0.56551724 0.56896552 0.57241379 0.57586207 0.57931034 0.58275862 0.5862069 0.58965517 0.59310345 0.59655172 0.6 0.60344828 0.60689655 0.61034483 0.6137931 0.61724138 0.62068966 0.62413793 0.62758621 0.63103448 0.63448276 0.63793103 0.64137931 0.64482759 0.64827586 0.65172414 0.65517241 0.65862069 0.66206897 0.66551724 0.66896552 0.67241379 0.67586207 0.67931034 0.68275862 0.6862069 0.68965517 0.69310345 0.69655172 0.7 0.70344828 0.70689655 0.71034483 0.7137931 0.71724138 0.72068966 0.72413793 0.72758621 0.73103448 0.73448276 0.73793103 0.74137931 0.74482759 0.74827586 0.75172414 0.75517241 0.75862069 0.76206897 0.76551724 0.76896552 0.77241379 0.77586207 0.77931034 0.78275862 0.7862069 0.78965517 0.79310345 0.79655172 0.8 0.80344828 0.80689655 0.81034483 0.8137931 0.81724138 0.82068966 0.82413793 0.82758621 0.83103448 0.83448276 0.83793103 0.84137931 0.84482759 0.84827586 0.85172414 0.85517241 0.85862069 0.86206897 0.86551724 0.86896552 0.87241379 0.87586207 0.87931034 0.88275862 0.8862069 0.88965517 0.89310345 0.89655172 0.9 0.90344828 0.90689655 0.91034483 0.9137931 0.91724138 0.92068966 0.92413793 0.92758621 0.93103448 0.93448276 0.93793103 0.94137931 0.94482759 0.94827586 0.95172414 0.95517241 0.95862069 0.96206897 0.96551724 0.96896552 0.97241379 0.97586207 0.97931034 0.98275862 0.9862069 0.98965517 0.99310345 0.99655172 1 1 1 1 1 1
  line L0 (173.4375, 0.4625) -> (173.4375, -0.4625)
  point P0 (172.7345, -0.5758)
  point P1 (170.6394, -0.9481)
  point P2 (167.1891, -1.6303)
  point P3 (162.4254, -2.627)
  point P4 (156.4013, -3.9128)
  point P5 (149.1817, -5.439)
  point P6 (140.8521, -7.1896)
  point P7 (131.5072, -9.1482)
  point P8 (121.2583, -11.2781)
  point P9 (110.2161, -13.5212)
  point P10 (98.5032, -15.8013)
  point P11 (86.2401, -18.0213)
  point P12 (73.5652, -20.091)
  point P13 (60.6199, -21.9156)
  point P14 (47.5542, -23.4141)
  point P15 (34.5233, -24.5056)
  point P16 (21.6936, -25.1207)
  point P17 (9.2269, -25.1947)
  point P18 (-2.701, -24.6744)
  point P19 (-13.9143, -23.5181)
  point P20 (-24.2304, -21.7097)
  point P21 (-33.4642, -19.2585)
  point P22 (-41.4261, -16.2245)
  point P23 (-47.9266, -12.7211)
  point P24 (-52.8083, -8.954)
  point P25 (-55.9579, -5.2494)
  point P26 (-57.4749, -2.0651)
  point P27 (-57.7431, 0.0416)
  point P28 (-57.7501, 0.7562)
  point P29 (-57.6229, 1.4245)
  point P30 (-56.2932, 3.0294)
  point P31 (-53.2222, 4.4284)
  point P32 (-48.6989, 5.6124)
  point P33 (-42.8529, 6.5328)
  point P34 (-35.7975, 7.2104)
  point P35 (-27.6321, 7.6474)
  point P36 (-18.4653, 7.8532)
  point P37 (-8.4106, 7.8371)
  point P38 (2.4096, 7.6197)
  point P39 (13.8634, 7.2196)
  point P40 (25.8168, 6.6577)
  point P41 (38.1308, 5.957)
  point P42 (50.6576, 5.1592)
  point P43 (63.2584, 4.3105)
  point P44 (75.7829, 3.4549)
  point P45 (88.0877, 2.6362)
  point P46 (100.0318, 1.8893)
  point P47 (111.4741, 1.2418)
  point P48 (122.2804, 0.7146)
  point P49 (132.3259, 0.3191)
  point P50 (141.4903, 0.0532)
  point P51 (149.665, -0.0833)
  point P52 (156.7528, -0.1041)
  point P53 (162.6682, -0.0254)
  point P54 (167.3417, 0.1133)
  point P55 (170.7157, 0.2729)
  point P56 (172.7553, 0.4093)
ref_plane "WorkPlane3" through (0, 400, 0) normal (0, 1, 0) x (0, 0, 1) in component "Wing OML (SD7062, 2 m)"
sketch "Section y=400" plane through (0, 400, 0) normal (0, 1, 0) x (1, 0, 0) in component "Wing OML (SD7062, 2 m)"
  spline S0 degree 5 poles (173.4375, -0.4625) (173.3779, -0.4713) (173.2398, -0.4925) (172.9754, -0.5349) (172.508, -0.6131) (171.7554, -0.7438) (170.8834, -0.9011) (169.9408, -1.0785) (168.9525, -1.2718) (167.9224, -1.4794) (166.8445, -1.7007) (165.7141, -1.9352) (164.5339, -2.1819) (163.3097, -2.4395) (162.0489, -2.7065) (160.7573, -2.9816) (159.4376, -3.2638) (158.0906, -3.5521) (156.7161, -3.8459) (155.3137, -4.1446) (153.8838, -4.4479) (152.4278, -4.7557) (150.9472, -5.0677) (149.4441, -5.3839) (147.9201, -5.7042) (146.3763, -6.0287) (144.8138, -6.3571) (143.2329, -6.6894) (141.6342, -7.0253) (140.018, -7.3648) (138.3848, -7.7076) (136.7352, -8.0536) (135.0699, -8.4027) (133.3896, -8.7546) (131.695, -9.1091) (129.9867, -9.4661) (128.2654, -9.8252) (126.5313, -10.1863) (124.7851, -10.5491) (123.0268, -10.9133) (121.257, -11.2787) (119.476, -11.645) (117.684, -12.012) (115.8816, -12.3794) (114.069, -12.747) (112.2468, -13.1147) (110.4153, -13.482) (108.5748, -13.8487) (106.7256, -14.2145) (104.8681, -14.5791) (103.0025, -14.942) (101.1291, -15.3029) (99.248, -15.6615) (97.3595, -16.0174) (95.464, -16.3704) (93.5617, -16.7202) (91.6529, -17.0666) (89.7379, -17.4093) (87.817, -17.7482) (85.8906, -18.083) (83.9589, -18.4134) (82.0221, -18.7393) (80.0807, -19.0603) (78.1347, -19.376) (76.1844, -19.6862) (74.2301, -19.9906) (72.2721, -20.2889) (70.3105, -20.5809) (68.3457, -20.8663) (66.3779, -21.1449) (64.4074, -21.4165) (62.4345, -21.681) (60.4595, -21.9381) (58.4827, -22.1876) (56.5043, -22.4294) (54.5246, -22.663) (52.5438, -22.8882) (50.5622, -23.1048) (48.5801, -23.3125) (46.5977, -23.511) (44.6154, -23.7) (42.6334, -23.8794) (40.6522, -24.0488) (38.6719, -24.2081) (36.693, -24.357) (34.7157, -24.4954) (32.7404, -24.6228) (30.7674, -24.7392) (28.797, -24.8442) (26.8296, -24.9374) (24.8654, -25.0186) (22.9047, -25.0875) (20.948, -25.1438) (18.9955, -25.1871) (17.0477, -25.2173) (15.1049, -25.2339) (13.1675, -25.2367) (11.2361, -25.2255) (9.3109, -25.1999) (7.3926, -25.1595) (5.4815, -25.104) (3.5781, -25.0329) (1.683, -24.9459) (-0.2034, -24.8426) (-2.0806, -24.7225) (-3.948, -24.5852) (-5.8051, -24.4305) (-7.6513, -24.2579) (-9.4861, -24.0673) (-11.3088, -23.8582) (-13.1187, -23.6303) (-14.9152, -23.3831) (-16.6973, -23.1162) (-18.4643, -22.8288) (-20.2152, -22.5205) (-21.949, -22.1905) (-23.6649, -21.8383) (-25.3618, -21.4636) (-27.039, -21.0661) (-28.6954, -20.6457) (-30.3303, -20.2023) (-31.9423, -19.7357) (-33.5302, -19.2456) (-35.0925, -18.7312) (-36.627, -18.1914) (-38.1316, -17.6252) (-39.604, -17.0314) (-41.0421, -16.4093) (-42.4441, -15.7591) (-43.8086, -15.0816) (-45.1342, -14.3787) (-46.4193, -13.6517) (-47.6616, -12.9015) (-48.8572, -12.1275) (-50.0006, -11.3267) (-51.0851, -10.4957) (-52.1043, -9.6324) (-53.0531, -8.7378) (-53.9292, -7.819) (-54.7331, -6.8893) (-55.4645, -5.9614) (-56.1187, -5.043) (-56.6829, -4.1292) (-57.135, -3.2016) (-57.4573, -2.2557) (-57.647, -1.3186) (-57.7297, -0.4816) (-57.7502, 0.1595) (-57.7499, 0.5935) (-57.7591, 0.9541) (-57.6812, 1.3907) (-57.3606, 1.9785) (-56.7919, 2.6466) (-56.042, 3.2659) (-55.1817, 3.7543) (-54.2419, 4.1256) (-53.2361, 4.4315) (-52.167, 4.7287) (-51.04, 5.0349) (-49.8616, 5.3437) (-48.6381, 5.6364) (-47.3752, 5.8957) (-46.0767, 6.118) (-44.7453, 6.3081) (-43.3825, 6.4756) (-41.9898, 6.6308) (-40.5684, 6.7797) (-39.1198, 6.9232) (-37.6457, 7.0599) (-36.1476, 7.1866) (-34.6269, 7.3004) (-33.0848, 7.4001) (-31.5223, 7.4862) (-29.9403, 7.5603) (-28.3396, 7.6242) (-26.721, 7.6798) (-25.085, 7.7285) (-23.4324, 7.7706) (-21.764, 7.8062) (-20.0803, 7.8348) (-18.3821, 7.8561) (-16.6699, 7.8697) (-14.9443, 7.8758) (-13.2058, 7.8746) (-11.455, 7.8666) (-9.6924, 7.8523) (-7.9183, 7.8323) (-6.1333, 7.807) (-4.3378, 7.7766) (-2.5322, 7.7412) (-0.7169, 7.701) (1.1075, 7.6558) (2.9408, 7.6059) (4.7825, 7.5511) (6.6322, 7.4917) (8.4896, 7.4277) (10.3544, 7.3594) (12.2261, 7.2869) (14.1044, 7.2105) (15.9891, 7.1303) (17.8799, 7.0463) (19.7763, 6.9588) (21.6781, 6.8677) (23.5851, 6.7731) (25.4968, 6.6752) (27.4131, 6.5739) (29.3335, 6.4694) (31.2577, 6.3619) (33.1855, 6.2515) (35.1166, 6.1385) (37.0505, 6.023) (38.9871, 5.9052) (40.9261, 5.7853) (42.8672, 5.6634) (44.8102, 5.5398) (46.7548, 5.4146) (48.7007, 5.288) (50.6479, 5.1601) (52.5959, 5.031) (54.5445, 4.901) (56.4935, 4.77) (58.4425, 4.6383) (60.3913, 4.506) (62.3396, 4.3733) (64.2871, 4.2403) (66.2334, 4.1071) (68.1784, 3.9738) (70.1218, 3.8408) (72.0632, 3.708) (74.0025, 3.5758) (75.9394, 3.4441) (77.8737, 3.3132) (79.805, 3.1832) (81.7331, 3.0542) (83.6577, 2.9264) (85.5785, 2.7997) (87.4953, 2.6744) (89.4077, 2.5506) (91.3155, 2.4284) (93.2183, 2.3078) (95.1159, 2.189) (97.0078, 2.0721) (98.8938, 1.9573) (100.7736, 1.8446) (102.6468, 1.7341) (104.5131, 1.626) (106.3722, 1.5203) (108.2237, 1.4171) (110.0673, 1.3165) (111.9026, 1.2186) (113.7293, 1.1235) (115.5469, 1.0314) (117.3551, 0.9423) (119.1534, 0.8564) (120.9414, 0.7738) (122.7188, 0.6946) (124.485, 0.6187) (126.2397, 0.5463) (127.9825, 0.4773) (129.713, 0.4117) (131.4306, 0.3496) (133.1347, 0.2909) (134.8248, 0.2358) (136.5002, 0.1844) (138.1601, 0.1368) (139.8038, 0.0932) (141.4307, 0.0536) (143.0402, 0.0183) (144.6317, -0.0128) (146.205, -0.0397) (147.7594, -0.0622) (149.2942, -0.0805) (150.8084, -0.0944) (152.3002, -0.1041) (153.7678, -0.1093) (155.2095, -0.1099) (156.6237, -0.1059) (158.0095, -0.0971) (159.3671, -0.0834) (160.6968, -0.0647) (161.9979, -0.041) (163.2682, -0.0127) (164.5022, 0.0197) (165.6923, 0.0553) (166.8319, 0.0935) (167.9171, 0.1343) (168.9516, 0.1785) (169.9416, 0.2275) (170.8846, 0.2813) (171.7577, 0.3377) (172.5117, 0.3908) (172.9791, 0.4257) (173.2421, 0.4462) (173.3788, 0.4575) (173.4375, 0.4625) knots 0 0 0 0 0 0 0.00344828 0.00689655 0.01034483 0.0137931 0.01724138 0.02068966 0.02413793 0.02758621 0.03103448 0.03448276 0.03793103 0.04137931 0.04482759 0.04827586 0.05172414 0.05517241 0.05862069 0.06206897 0.06551724 0.06896552 0.07241379 0.07586207 0.07931034 0.08275862 0.0862069 0.08965517 0.09310345 0.09655172 0.1 0.10344828 0.10689655 0.11034483 0.1137931 0.11724138 0.12068966 0.12413793 0.12758621 0.13103448 0.13448276 0.13793103 0.14137931 0.14482759 0.14827586 0.15172414 0.15517241 0.15862069 0.16206897 0.16551724 0.16896552 0.17241379 0.17586207 0.17931034 0.18275862 0.1862069 0.18965517 0.19310345 0.19655172 0.2 0.20344828 0.20689655 0.21034483 0.2137931 0.21724138 0.22068966 0.22413793 0.22758621 0.23103448 0.23448276 0.23793103 0.24137931 0.24482759 0.24827586 0.25172414 0.25517241 0.25862069 0.26206897 0.26551724 0.26896552 0.27241379 0.27586207 0.27931034 0.28275862 0.2862069 0.28965517 0.29310345 0.29655172 0.3 0.30344828 0.30689655 0.31034483 0.3137931 0.31724138 0.32068966 0.32413793 0.32758621 0.33103448 0.33448276 0.33793103 0.34137931 0.34482759 0.34827586 0.35172414 0.35517241 0.35862069 0.36206897 0.36551724 0.36896552 0.37241379 0.37586207 0.37931034 0.38275862 0.3862069 0.38965517 0.39310345 0.39655172 0.4 0.40344828 0.40689655 0.41034483 0.4137931 0.41724138 0.42068966 0.42413793 0.42758621 0.43103448 0.43448276 0.43793103 0.44137931 0.44482759 0.44827586 0.45172414 0.45517241 0.45862069 0.46206897 0.46551724 0.46896552 0.47241379 0.47586207 0.47931034 0.48275862 0.4862069 0.48965517 0.49310345 0.49655172 0.5 0.50344828 0.50689655 0.51034483 0.5137931 0.51724138 0.52068966 0.52413793 0.52758621 0.53103448 0.53448276 0.53793103 0.54137931 0.54482759 0.54827586 0.55172414 0.55517241 0.55862069 0.56206897 0.56551724 0.56896552 0.57241379 0.57586207 0.57931034 0.58275862 0.5862069 0.58965517 0.59310345 0.59655172 0.6 0.60344828 0.60689655 0.61034483 0.6137931 0.61724138 0.62068966 0.62413793 0.62758621 0.63103448 0.63448276 0.63793103 0.64137931 0.64482759 0.64827586 0.65172414 0.65517241 0.65862069 0.66206897 0.66551724 0.66896552 0.67241379 0.67586207 0.67931034 0.68275862 0.6862069 0.68965517 0.69310345 0.69655172 0.7 0.70344828 0.70689655 0.71034483 0.7137931 0.71724138 0.72068966 0.72413793 0.72758621 0.73103448 0.73448276 0.73793103 0.74137931 0.74482759 0.74827586 0.75172414 0.75517241 0.75862069 0.76206897 0.76551724 0.76896552 0.77241379 0.77586207 0.77931034 0.78275862 0.7862069 0.78965517 0.79310345 0.79655172 0.8 0.80344828 0.80689655 0.81034483 0.8137931 0.81724138 0.82068966 0.82413793 0.82758621 0.83103448 0.83448276 0.83793103 0.84137931 0.84482759 0.84827586 0.85172414 0.85517241 0.85862069 0.86206897 0.86551724 0.86896552 0.87241379 0.87586207 0.87931034 0.88275862 0.8862069 0.88965517 0.89310345 0.89655172 0.9 0.90344828 0.90689655 0.91034483 0.9137931 0.91724138 0.92068966 0.92413793 0.92758621 0.93103448 0.93448276 0.93793103 0.94137931 0.94482759 0.94827586 0.95172414 0.95517241 0.95862069 0.96206897 0.96551724 0.96896552 0.97241379 0.97586207 0.97931034 0.98275862 0.9862069 0.98965517 0.99310345 0.99655172 1 1 1 1 1 1
  line L0 (173.4375, 0.4625) -> (173.4375, -0.4625)
  point P0 (172.7345, -0.5758)
  point P1 (170.6394, -0.9481)
  point P2 (167.1891, -1.6303)
  point P3 (162.4254, -2.627)
  point P4 (156.4013, -3.9128)
  point P5 (149.1817, -5.439)
  point P6 (140.8521, -7.1896)
  point P7 (131.5072, -9.1482)
  point P8 (121.2583, -11.2781)
  point P9 (110.2161, -13.5212)
  point P10 (98.5032, -15.8013)
  point P11 (86.2401, -18.0213)
  point P12 (73.5652, -20.091)
  point P13 (60.6199, -21.9156)
  point P14 (47.5542, -23.4141)
  point P15 (34.5233, -24.5056)
  point P16 (21.6936, -25.1207)
  point P17 (9.2269, -25.1947)
  point P18 (-2.701, -24.6744)
  point P19 (-13.9143, -23.5181)
  point P20 (-24.2304, -21.7097)
  point P21 (-33.4642, -19.2585)
  point P22 (-41.4261, -16.2245)
  point P23 (-47.9266, -12.7211)
  point P24 (-52.8083, -8.954)
  point P25 (-55.9579, -5.2494)
  point P26 (-57.4749, -2.0651)
  point P27 (-57.7431, 0.0416)
  point P28 (-57.7501, 0.7562)
  point P29 (-57.6229, 1.4245)
  point P30 (-56.2932, 3.0294)
  point P31 (-53.2222, 4.4284)
  point P32 (-48.6989, 5.6124)
  point P33 (-42.8529, 6.5328)
  point P34 (-35.7975, 7.2104)
  point P35 (-27.6321, 7.6474)
  point P36 (-18.4653, 7.8532)
  point P37 (-8.4106, 7.8371)
  point P38 (2.4096, 7.6197)
  point P39 (13.8634, 7.2196)
  point P40 (25.8168, 6.6577)
  point P41 (38.1308, 5.957)
  point P42 (50.6576, 5.1592)
  point P43 (63.2584, 4.3105)
  point P44 (75.7829, 3.4549)
  point P45 (88.0877, 2.6362)
  point P46 (100.0318, 1.8893)
  point P47 (111.4741, 1.2418)
  point P48 (122.2804, 0.7146)
  point P49 (132.3259, 0.3191)
  point P50 (141.4903, 0.0532)
  point P51 (149.665, -0.0833)
  point P52 (156.7528, -0.1041)
  point P53 (162.6682, -0.0254)
  point P54 (167.3417, 0.1133)
  point P55 (170.7157, 0.2729)
  point P56 (172.7553, 0.4093)
ref_plane "WorkPlane4" through (0, 1000, 0) normal (0, 1, 0) x (0, 0, 1) in component "Wing OML (SD7062, 2 m)"